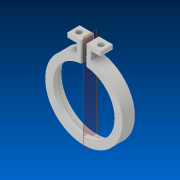
# Autodesk Inventor part: Lower housing
Saved by Autodesk Inventor 2019 (Build 230136000, 136)
## iProperties
Created: 2019-04-17
Part Number: Lower housing
Material: Generic
Document SubType Name: Modeling
Designer: --------
Density: 1 g/cm^3
Appearance: Default
Author: --------
Autodesk Inventor part; units mm, degrees
ref_plane "YZ Plane" through (0, 0, 0) normal (1, 0, 0) x (0, 1, 0)
ref_plane "XZ Plane" through (0, 0, 0) normal (0, 1, 0) x (-1, 0, 0)
ref_plane "XY Plane" through (0, 0, 0) normal (0, 0, 1) x (1, 0, 0)
sketch "Sketch1" plane through (0, 0, 0) normal (0, 0, 1) x (1, 0, 0)
  circle A0 centre (0, 0) radius 25.5
  circle A1 centre (0, 0) radius 28
  dimension "d0" = 51
  dimension "d1" = 56
  constraints: 2 centre point, 2 coincident
  measures "d0" diameter of A0
  measures "d1" diameter of A1
extrude "Extrusion1" add sketch "Sketch1" along normal blind 6
sketch "Sketch2" plane through (0, 0, 6) normal (0, 0, 1) x (1, 0, 0)
  circle A0 centre (0, 0) radius 23
  circle A1 centre (0, 0) radius 28 projected
  dimension "d4" = 46
  constraints: 1 centre point, 1 coincident
  measures "d4" diameter of A0
extrude "Extrusion2" add sketch "Sketch2" along normal blind 3
sketch "Sketch4" plane through (0, 0, 9) normal (0, 0, 1) x (1, 0, 0)
  circle A0 centre (0, 0) radius 28 projected
  circle A1 centre (0, 0) radius 23 projected
  line L0 (-28, 0) -> (31.461, 0)
  line L1 (31.461, 0) -> (31.461, 29.4467)
  line L2 (31.461, 29.4467) -> (-28, 29.4467)
  line L3 (-28, 29.4467) -> (-28, 0)
  constraints: 8 end point, 2 parallel, 1 horizontal, 1 horizontal alignment, 1 perpendicular, 1 other
extrude "Extrusion3" cut sketch "Sketch4" against normal blind 50 contours L0 A1 A0 | A0 L3 L2 L1 L0 | L0 A1 picked at (-26.0621, 2.2336) picked at (5.7386, 5.0839)
sketch "Sketch12" plane through (-28, 0, 9) normal (0, 1, 0) x (1, 0, 0)
  line L0 (0, 9) -> (0, 0) projected
  line L1 (2.5, 9) -> (2.5, 3) projected
  line L2 (0, 9) -> (2.5, 9) projected
  line L3 (5, 3) -> (5, 0) projected
  line L4 (2.5, 3) -> (5, 3) projected
  line L5 (5, 0) -> (0, 0) projected
  line L6 (28, 9) -> (28, 17.8273)
  constraints: 2 end point, 1 vertical
revolve "Revolution3" add sketch "Sketch12" angle 360 about axis through (0, 0, 0) along (0, 0, -1)
sketch "Sketch13" plane through (0, 0, 9) normal (0, 0, 1) x (1, 0, 0)
  circle A0 centre (0, 0) radius 25.5 projected
  circle A1 centre (0, 0) radius 23 projected
  circle A2 centre (0, 0) radius 28 projected
  circle A3 centre (0, 0) radius 23 projected
  line L0 (0, 23) -> (0, 29.7095)
  line L1 (0, 29.7095) -> (2, 29.7095)
  line L2 (2, 29.7095) -> (2, 19.0359)
  line L3 (2, 19.0359) -> (-2, 19.0359)
  line L4 (-2, 19.0359) -> (-2, 29.7095)
  line L5 (-2, 29.7095) -> (0, 29.7095)
  dimension "d35" = 2
  dimension "d36" = 4
  constraints: 12 end point, 4 perpendicular, 1 horizontal, 1 point on line, 1 vertical, 1 vertical alignment, 1 other
  measures "d35" distance of L0.end L1.end
  measures "d36" distance of L2.end L3.end
extrude "Extrusion8" cut sketch "Sketch13" against normal blind 10 contours L2 A1 L0 A0 | A0 L0 A2 L2 | L4 A2 L0 A0 | A0 L0 A1 L4 | A2 L0 L1 L2 | L2 L3 L4 A1 | L4 L5 L0 A2 picked at (0, 20.3573)
sketch "Sketch14" plane through (0, 0, 9) normal (0, 0, 1) x (1, 0, 0)
  line L0 (-2, 22.9129) -> (-2, 27.9285) projected
  arc A0 (-2, 27.9285) -> (2, 27.9285) centre (0, 0) ccw projected
  line L1 (2, 27.9285) -> (2, 22.9129) projected
  arc A1 (-2, 22.9129) -> (2, 22.9129) centre (0, 0) ccw projected
  arc A2 (-2, 25.4214) -> (2, 25.4214) centre (0, 0) ccw projected
  line L2 (-2, 27.9285) -> (-2, 33.9285)
  line L3 (-2, 33.9285) -> (-2, 36.9285)
  line L4 (-2, 36.9285) -> (-12, 36.9285)
  line L5 (-12, 36.9285) -> (-12, 33.9285)
  line L6 (-12, 33.9285) -> (-5, 33.9285)
  line L7 (-5, 33.9285) -> (-5, 26.9567)
  line L8 (-5, 26.9567) -> (-2, 26.9567)
  dimension "d39" = 6
  dimension "d40" = 3
  dimension "d41" = 10
  dimension "d42" = 3
  dimension "d43" = 7
  constraints: 14 end point, 5 perpendicular, 2 vertical, 1 point on line
  measures "d39" distance of L0.end L2.end
  measures "d40" distance of L2.end L3.end
  measures "d41" distance of L3.end L4.end
  measures "d42" distance of L4.end L5.end
  measures "d43" distance of L5.end L6.end
extrude "Extrusion9" add sketch "Sketch14" against normal blind 9 contours L8 L7 A0 L0 | A0 L7 L6 L5 L4 L3 L2
sketch "Sketch15" plane through (-12, 36.9285, 9) normal (0, 1, 0) x (1, 0, 0)
  line L0 (10, 0) -> (0, 0) projected
  line L1 (10, 0) -> (10, 9) projected
  line L2 (0, 9) -> (10, 9) projected
  line L3 (0, 0) -> (0, 9) projected
  line L4 (0, 0) -> (0, 9) projected
  line L5 (0, 4.5) -> (4, 4.5)
  circle A0 centre (4, 4.5) radius 2
  point P0 (12, 9)
  dimension "d46" = 4
  dimension "d47" = 4
  constraints: 2 end point, 1 centre point, 1 coincident, 1 horizontal, 1 midpoint
  measures "d46" distance of L5.start L5.end
  measures "d47" diameter of A0
extrude "Extrusion10" cut sketch "Sketch15" against normal blind 5 contours A0
ref_plane "Work Plane1" through (0, 22.9129, 9) normal (-1, 0, 0) x (0, 0, 1)
mirror "Mirror3" about plane through (0, 22.9129, 9) normal (-1, 0, 0) of "Extrusion9", "Extrusion10"
fillet "Fillet2" radius 1 1 edges at (0, -25.5, 6)
sketch "Sketch16" plane through (0, 0, 6) normal (0, 0, -1) x (-1, 0, 0)
  arc A0 (-2, 22.9129) -> (2, 22.9129) centre (0, 0) ccw projected
  arc A1 (-2, 22.9129) -> (2, 22.9129) centre (0, 0) ccw
  arc A2 (-2, 22.4109) -> (2, 22.4109) centre (0, 0) ccw
  line L0 (2, 24.4182) -> (2, 22.9129) projected
  line L1 (2, 22.9129) -> (2, 22.4109)
  line L2 (-2, 22.9129) -> (-2, 22.4109)
  dimension "d51" = 45
  constraints: 4 end point, 4 point on circle, 2 centre point, 2 coincident, 1 collinear, 1 concentric, 1 vertical
  measures "d51" diameter of A2
extrude "Extrusion11" add sketch "Sketch16" against normal blind 3
body "Solid1"
